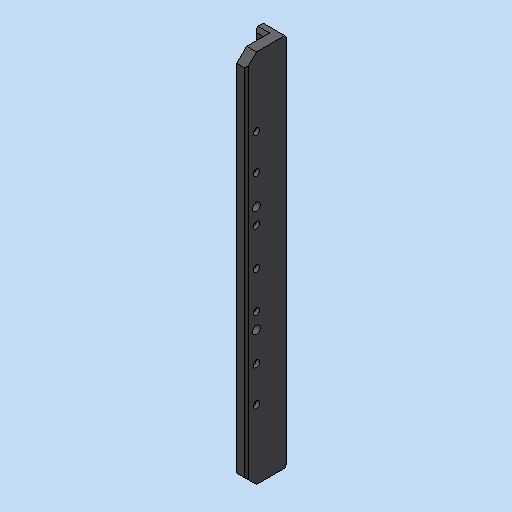
# Autodesk Inventor part: MM0861AN100_G01_119
Saved by Autodesk Inventor 2023.3 (Build 273359000, 359)
## iProperties
Created: 2018-11-05
Part Number: MM0861AN100_G01_119
Material: 1.2379 X155CrVMo12-1
Document SubType Name: Modeling
Designer: Rose
Density: 7.85 g/cm^3
Appearance: Blau-H
Mass: 188.266 g
Surface Area: 123.653 cm^2
Volume: 23.9829 cm^3
Description: =<RBPARTNOTITLE2>
RBMATERIAL: =<Material>
RBMATNO: =<Part Number>
RBPARTMADEOF: Präzi.Fl.25x12x193
RBPARTNOTITLE1: manufactured part
RBPARTNOTITLE2: Anfertigungsteil
MaxAbmaße: 0 x 0 x 0 (FM)
AnP_Material_aktuell: =<Material>
AnP_Kommentar_aktuell: =<Comments>
RBDRAWINGMISSINGSPEC: --
AnP_Kategorie: 1
AnP_Material: =<Material>
RBSURFACE2: HRC 56±2
Author: Rose
Keywords: =<RBPARTMADEOF>
Comments: =<RBSURFACE2>
Revision Number: 01
Autodesk Inventor part; units mm, degrees
ref_plane "YZ Plane" through (0, 0, 0) normal (1, 0, 0) x (0, 1, 0)
ref_plane "XZ Plane" through (0, 0, 0) normal (0, 1, 0) x (-1, 0, 0)
ref_plane "XY Plane" through (0, 0, 0) normal (0, 0, 1) x (1, 0, 0)
sketch "Skizze1" plane through (0, 0, 0) normal (0, 0, 1) x (1, 0, 0)
  line L0 (0, 19.6) -> (0, -9.1) projected
  line L1 (-13.2, 0) -> (2.2, 0) projected
  line L2 (0, -5) -> (0, 15.5)
  line L3 (0, 15.5) -> (-11, 15.5)
  line L4 (-11, 15.5) -> (-11, 10.5)
  line L5 (-11, 10.5) -> (-5, 10.5)
  line L6 (-5, 10.5) -> (-5, -5)
  line L7 (-5, -5) -> (0, -5)
  dimension "d0" = 5
  dimension "d1" = 11
  dimension "d2" = 5
  dimension "d3" = 5
  dimension "d4" = 15.5
  constraints: 12 end point, 3 perpendicular, 2 parallel, 2 point on line
  measures "d0" distance between parallel lines of L5 L3
  measures "d1" distance between parallel lines of L2 L4
  measures "d2" distance between parallel lines of L0 L6
  measures "d3" distance between parallel lines of L7 L1
  measures "d4" distance between parallel lines of L1 L3
extrude "Extrusion1" add sketch "Skizze1" along normal mid plane 190
sketch "Skizze2" plane through (-5, -5, 95) normal (-1, 0, 0) x (0, 0, 1)
  line L0 (-228, 5) -> (38, 5) projected
  line L1 (-95, 24.6) -> (-95, -4.1) projected
  point P0 (-114, 5)
  point P1 (-155, 5)
  point P2 (-76, 5)
  point P3 (-35, 5)
  point P4 (-137, 5)
  point P5 (-53, 5)
  point P6 (-95, 5)
  dimension "d7" = 38
  dimension "d8" = 120
  dimension "d39" = 84
  constraints: 3 symmetric about line, 1 point on line, 8 other
  measures "d7" distance of point (-76, 5) point (-114, 5)
  measures "d8" distance of point (-155, 5) point (-35, 5)
  measures "d39" distance of point (-53, 5) point (-137, 5)
hole "Bohrung1" at (-5, 0, -19) at (-5, 0, -60) at (-5, 0, 19) at (-5, 0, 60) at (-5, 0, -42) at (-5, 0, 42) at (-5, 0, 0) direction (1, 0, 0) diameter 3.4 end through all counterbore diameter 6 counterbore depth 3.2
sketch "Skizze3" plane through (0, -5, 95) normal (1, 0, 0) x (0, 0, -1)
  line L0 (95, -4.1) -> (95, 24.6) projected
  circle A0 centre (35, 5) radius 1.7 projected
  line L1 (35, 5) -> (68, 5)
  point P0 (122, 5)
  dimension "d16" = 54
  constraints: 2 end point, 1 coincident, 1 perpendicular, 1 symmetric about line
  measures "d16" distance of point (122, 5) point (68, 5)
hole "Bohrung2" at (0, 0, 27) at (0, 0, -27) direction (-1, 0, 0) diameter 3.5 end through all counterbore diameter 4 counterbore depth 4
chamfer "Fase1" distance 0.5 angle 45 3 edges at (-11, 10.5, 0) (-11, 15.5, 0) (0, 15.5, 0)
chamfer "Fase2" distance 1 angle 45 1 edges at (0, -5, 0)
chamfer "Fase3" distance 2 angle 30 2 edges at (-7.75, 10.5, 95) (-7.75, 10.5, -95) measured on face at (-8.6667, 10.5, 31.6667)
chamfer "Fase4" distance 2 angle 30 2 edges at (-5.5, 15.5, 95) (-5.5, 15.5, -95) measured on face at (-3.8333, 15.5, 31.6667)
chamfer "Fase5" distance 5 angle 45 2 edges at (-3, -5, 95) (-3, -5, -95)
